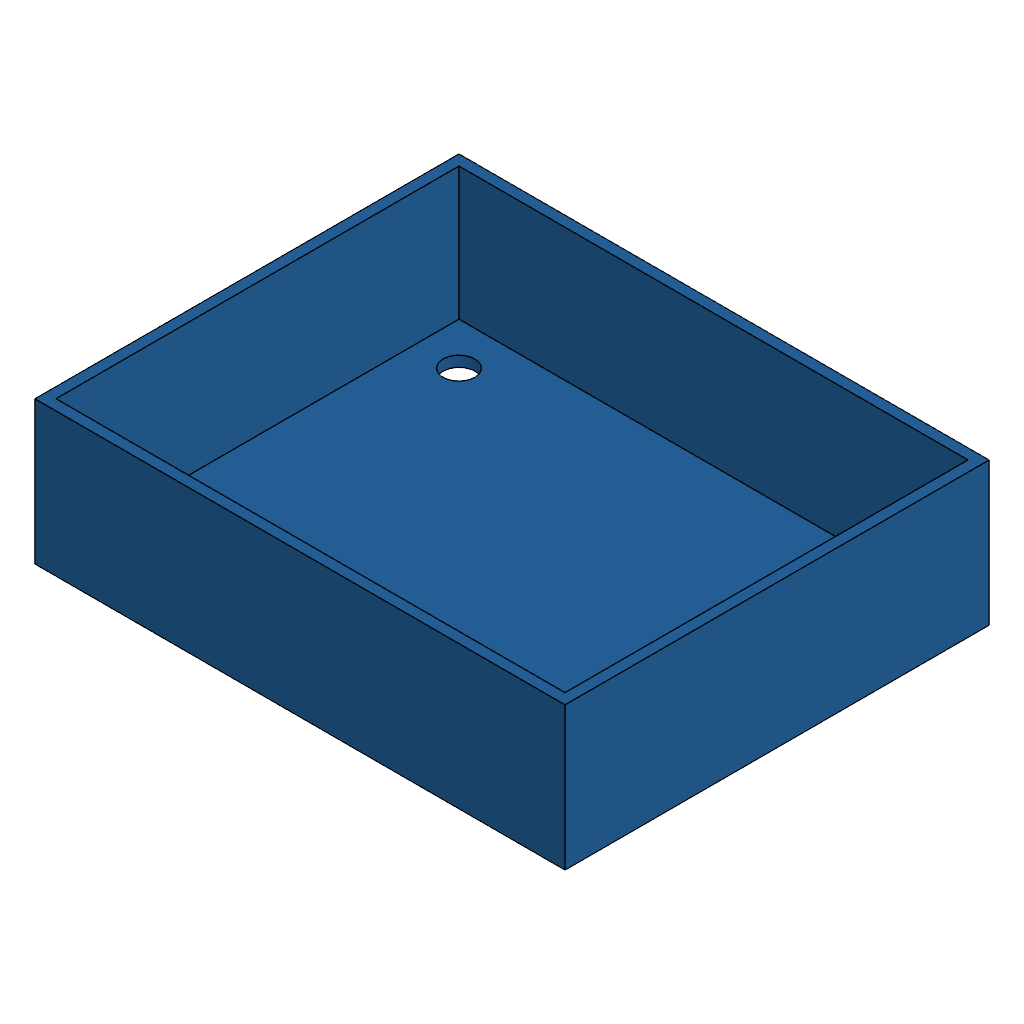
sketched_box (Autodesk Fusion 360 design; units mm, degrees)
Autodesk Fusion 360 part; units mm, degrees
sketch "outline" plane through (0, 0, 0) normal (0, 0, 1) x (1, 0, 0)
  line L0 (-50, -40) -> (50, -40)
  line L1 (50, -40) -> (50, 40)
  line L2 (50, 40) -> (-50, 40)
  line L3 (-50, 40) -> (-50, -40)
  line L4 (-50, -40) -> (50, 40) construction
  dimension "d7" = 100
  dimension "d8" = 80
  constraint horizontal L0
  constraint horizontal L2
  constraint vertical L1
  constraint vertical L3
  constraint midpoint origin L4
  measures "d7" horizontal distance of L0.start L0.end
  measures "d8" vertical distance of L0.end L1.end
extrude "Extrude1" add sketch "outline" along normal blind 27
shell "Shell1" thickness 2 removed faces 1 at (-16.6667, 13.3333, 27)
sketch "floor holes" plane through (0, 0, 0) normal (0, 0, 1) x (1, 0, 0)
  circle A0 centre (-40, -30) radius 3
  circle A1 centre (-40, 30) radius 3
  circle A2 centre (40, -30) radius 3
  circle A3 centre (40, 30) radius 3
extrude "Extrude2" cut sketch "floor holes" along normal blind 2
equation "length = 100 mm" comment "outer length (the 100 on the sketch)"
equation "width = 80 mm" comment "outer width (the 80)"
equation "height = 27 mm" comment "outer height (the 27)"
equation "wall = 2 mm" comment "wall and floor thickness ('2mm thick')"
equation "hole_d = 6 mm" comment "hole diameter ('4 holes 6 mm')"
equation "hole_inset = 10 mm" comment "hole centre to outer edge (GUESS: not on the sketch)"
equation "d7 = length"
equation "d8 = width"
equation "d9 = height"
equation "d11 = wall"
equation "d12 = wall"
named bodies: "Tray"
